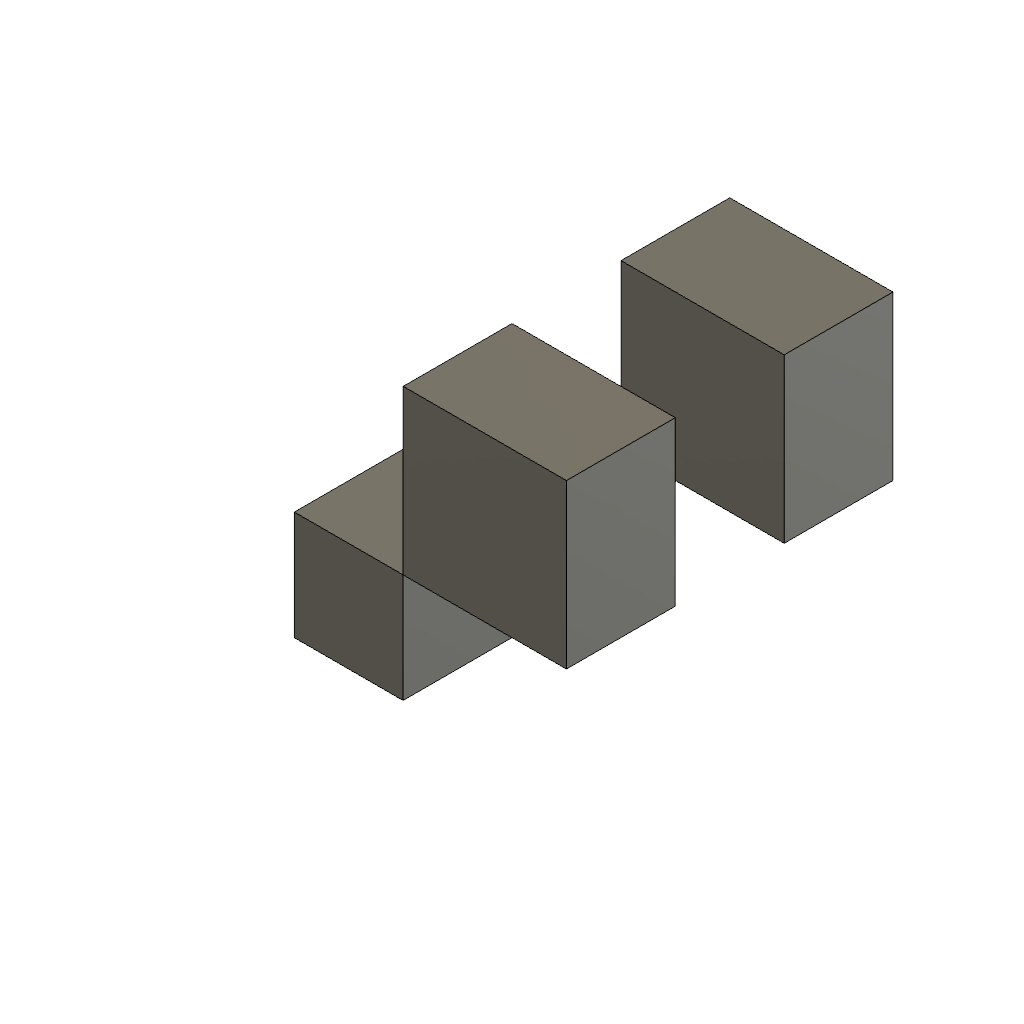
body_brep_face_plane (Autodesk Fusion 360 design; units mm, degrees)
part number: 2026-10-20-23-40-47-800
Autodesk Fusion 360 part; units mm, degrees
sketch "MirrorSeedSketch" plane through (0, 0, 0) normal (0, 0, 1) x (1, 0, 0)
  line L0 (10, 10) -> (40, 10)
  line L1 (40, 10) -> (40, 40)
  line L2 (40, 40) -> (10, 40)
  line L3 (10, 40) -> (10, 10)
extrude "MirrorSeedExtrude" add sketch "MirrorSeedSketch" along normal blind 20 makes body 1
sketch "MirrorPlaneSupportSketch" plane through (0, 0, 0) normal (0, 0, 1) x (1, 0, 0)
  line L0 (-40, -40) -> (-20, -40)
  line L1 (-20, -40) -> (-20, -20)
  line L2 (-20, -20) -> (-40, -20)
  line L3 (-40, -20) -> (-40, -40)
extrude "MirrorPlaneSupportExtrude" add sketch "MirrorPlaneSupportSketch" along normal blind 30 separate body makes body 2
mirror "ProbeMirrorFeatureModes" about plane through (0, 0, 30) normal (0, 0, 1) of bodies 1 makes body 3
named bodies: "MirrorSeedBody", "MirrorPlaneSupportBody", "MirrorSeedBody (1)"
